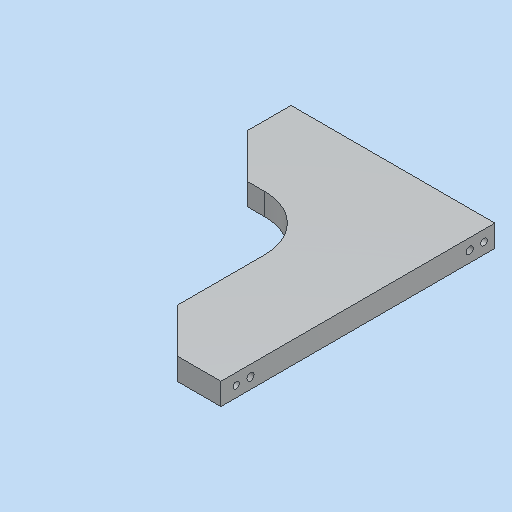
# Autodesk Inventor part: MM0948AN180_G01_101
Saved by Autodesk Inventor 2023.3 (Build 273359000, 359)
## iProperties
Part Number: MM0948AN180_G01_101
Material: 3.3547 AlMg4,5Mn0,7 - AW 5083
Description: =<RBPARTNOTITLE2>
Document SubType Name: Modeling
Designer: ric7an
Mass: 1471.68 g
Surface Area: 728.896 cm^2
Volume: 545.068 cm^3
Density: 2.7 g/cm^3
Appearance: Aluminium AnP
Created: 2023-03-23
RBDOCUMENTTYPE: DRF
RBDOCUMENTVERSION: 00
RBDRAWINGMAINSCALE: 1:1
RBDRAWINGMISSINGSPEC: --
RBDRAWINGVOLUME: --
RBGBEDGESIN1: +0,5
RBGBEDGESIN2: +0,2
RBGBEDGESOUT1: -0,3
RBGBEDGESOUT2: -0,1
RBMATERIAL: =<Material>
RBMATMEETS: --
RBMATNO: =<Part Number>
RBPARTMADEOF: 20 x 250 x 186 (FM)
RBPARTNO: SIEHE MNR
RBPARTNOTITLE1: manufactured part
RBPARTNOTITLE2: Anfertigungsteil
RBPARTSAFETYINDICATOR: --
RBSURFACE: anodised colourless
RBSURFACE2: eloxiert farblos
RBZEDGESNORM: ISO13715:2002-06
RBZGENDIMCLASS: m
RBZGENDIMNORM: ISO 2768-1:1989-11
RBZGENGEOCLASS: H
RBZGENGEONORM: ISO 2768-2:1989-11
RBZSURFACENORM: ISO13D2:2002-02
RBZTOLERANCENORM: ISO 14405-1:2010-12
AnP_Material: =<Material>
AnP_TemplVers: 20190222
AnP_Kategorie: 1
MaxAbmaße: 20 x 250 x 186 (FM)
AnP_Kommentar_aktuell: =<Comments>
AnP_Material_aktuell: =<Material>
Author: FH/Wi
Keywords: =<RBPARTMADEOF>
Comments: =<RBSURFACE2>
Revision Number: 01
Autodesk Inventor part; units mm, degrees
ref_plane "YZ Plane" through (0, 0, 0) normal (1, 0, 0) x (0, 1, 0)
ref_plane "XZ Plane" through (0, 0, 0) normal (0, 1, 0) x (-1, 0, 0)
ref_plane "XY Plane" through (0, 0, 0) normal (0, 0, 1) x (1, 0, 0)
sketch "Skizze1" plane through (0, 0, 0) normal (0, 0, 1) x (1, 0, 0)
  line L0 (0, 0) -> (186, 0)
  line L1 (186, 0) -> (186, 250)
  line L2 (186, 250) -> (0, 250)
  line L3 (0, 250) -> (0, 0)
  line L4 (0, 0) -> (106, 0)
  line L5 (106, 0) -> (106, 170)
  line L6 (106, 170) -> (0, 170)
  line L7 (0, 170) -> (0, 0)
  dimension "d0" = 250
  dimension "d1" = 186
  dimension "d2" = 80
  dimension "d3" = 80
  constraints: 16 end point, 4 parallel, 2 horizontal, 2 perpendicular
  measures "d0" distance of L0.end L1.end
  measures "d1" distance of L1.end L2.end
  measures "d2" distance between parallel lines of L2 L6
  measures "d3" distance between parallel lines of L1 L5
extrude "Extrusion1" add sketch "Skizze1" along normal mid plane 20 contours L5 L6 L3 L2 L1 L0
fillet "Rundung1" radius 50 1 edges at (106, 170, 0)
chamfer "Fase1" distance 40 angle 45 2 edges at (0, 170, 0) (106, 0, 0)
sketch "Skizze2" plane through (186, 0, 10) normal (1, 0, 0) x (0, 0, -1)
  line L0 (-4, 0) -> (24, 0) projected
  line L1 (10, -165.2) -> (10, 319.2) projected
  line L2 (20, 250) -> (0, 250) projected
  point P0 (10, 0)
  point P1 (10, 240)
  point P2 (10, 27)
  point P3 (10, 227)
  point P4 (10, 14)
  dimension "d11" = 10
  dimension "d13" = 200
  dimension "d14" = 13
  dimension "d38" = 13
  constraints: 2 point on line, 2 vertical alignment
  measures "d11" distance from line of L2 point (10, 240)
  measures "d13" distance of point (10, 227) point (10, 27)
  measures "d14" distance of point (10, 240) point (10, 227)
  measures "d38" distance of point (10, 27) point (10, 14)
hole "Bohrung1" at (186, 27, 0) at (186, 227, 0) direction (-1, 0, 0) diameter 6.647 depth 22.2 tip angle 118 thread size "M8x1.25" designation "M8" class "6H" standard "ISO Metric profile"
hole "Bohrung2" at (186, 240, 0) at (186, 14, 0) direction (-1, 0, 0) diameter 6 depth 15 tip angle 118
sketch "Skizze3" plane through (0, 250, 10) normal (0, 1, 0) x (1, 0, 0)
  line L0 (0, 24) -> (0, -4) projected
  line L1 (223.2, 10) -> (-37.2, 10) projected
  line L2 (186, 20) -> (186, 0) projected
  point P0 (0, 10)
  point P1 (26, 10)
  dimension "d30" = 160
  constraints: 1 point on line
  measures "d30" distance from line of L2 point (26, 10)
hole "Bohrung3" at (26, 250, 0) direction (0, -1, 0) diameter 6.647 depth 22.2 tip angle 118 thread size "M8x1.25" designation "M8" class "6H" standard "ISO Metric profile"
equation "\"d14\" = -0.5 * d12 + 0.5 * d10"
equation "\"d38\" = d14"
equation "\"d12\" = 250"
equation "\"d10\" = 276"
